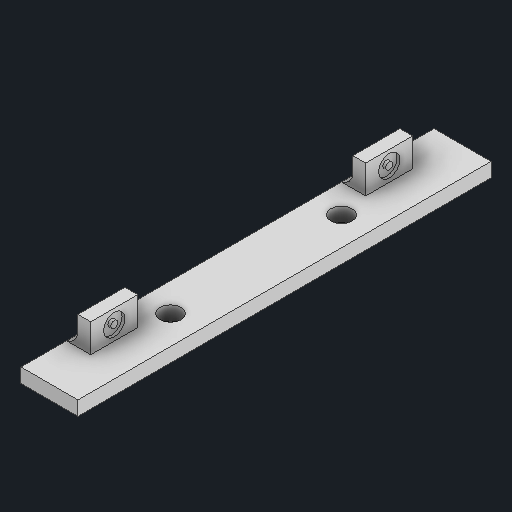
# Autodesk Inventor part: 扭力模块板1
Saved by Autodesk Inventor 2025 (Build 290162000, 162)
## iProperties
Created: 2025-08-27
Part Number: 扭力模块板1
Material: 常规
Document SubType Name: Modeling
Designer: HZD
Density: 1 g/cm^3
Appearance: 默认
Author: HZD
Autodesk Inventor part; units mm, degrees
ref_plane "YZ Plane" through (0, 0, 0) normal (1, 0, 0) x (0, 1, 0)
sketch "草图1" plane through (0, 0, 0) normal (0, 0, 1) x (1, 0, 0)
  line L0 (2, -0.5) -> (-2, -0.5)
  line L1 (-2, -0.5) -> (-2, 0.5)
  line L2 (-2, 0.5) -> (2, 0.5)
  line L3 (2, 0.5) -> (2, -0.5)
  line L4 (2, -0.5) -> (-2, 0.5) construction
  line L5 (-2, -0.5) -> (2, 0.5) construction
  point P0 (0, 0)
  dimension "d0" = 1
  dimension "d1" = 4
  constraints: 12 end point, 2 midpoint, 2 parallel, 1 horizontal, 1 perpendicular
  measures "d0" distance of L2.end L0.start
  measures "d1" distance of L1.end L2.end
extrude "拉伸1" add sketch "草图1" along normal blind 15
sketch "草图2" plane through (-2, 0.5, 0) normal (0, 1, 0) x (1, 0, 0)
  circle A0 centre (2, -13.5) radius 0.75 projected
  circle A1 centre (1.9693, -7.446) radius 0.75 projected
  line L0 (4, 0) -> (0, 0) projected
  line L1 (0, 0) -> (0, -15) projected
  line L2 (4, -15) -> (0, -15) projected
  line L3 (4, 0) -> (4, -15) projected
  circle A2 centre (2, -1.5) radius 0.75 projected
  point P0 (2, 0)
extrude "拉伸2" cut sketch "草图2" against normal blind 15 contours A0 | A2
sketch "草图3" plane through (-2, 0.5, 0) normal (0, 1, 0) x (1, 0, 0)
  line L0 (4, -15) -> (0, -15) projected
  line L1 (0, -15) -> (4, -15)
  line L2 (4, -15) -> (4, -22)
  line L3 (4, -22) -> (0, -22)
  line L4 (0, -22) -> (0, -15)
  line L5 (0, 0) -> (0, -15) projected
  line L6 (0, -7.5) -> (8.0823, -7.5)
  line L7 (4, 0) -> (0, 0)
  line L8 (0, 0) -> (4, 0)
  line L9 (4, 0) -> (4, 7)
  line L10 (4, 7) -> (0, 7)
  line L11 (0, 7) -> (0, 0)
  point P0 (2, 0)
  dimension "d6" = 7
  constraints: 20 end point, 4 symmetric about line, 2 horizontal, 2 parallel, 1 midpoint, 1 perpendicular
  measures "d6" distance of L1.end L2.end
extrude "拉伸3" add sketch "草图3" against normal up to surface (1 mm away)
ref_plane "工作平面2" through (-2.5, 2.1, 0) normal (0, 1, 0) x (0, 0, 1)
sketch "草图4" plane through (-2, 0.5, 22) normal (0, 1, 0) x (1, 0, 0)
  line L0 (4, 22) -> (2, 22)
  line L1 (2, 22) -> (2, 26.3024)
  line L2 (2, 26.3024) -> (4, 26.3024)
  line L3 (4, 26.3024) -> (4, 22)
  line L4 (2, 25.8024) -> (4, 25.8024)
  line L5 (2, 22.5) -> (4, 22.5)
  line L6 (0, 29) -> (0, 0) projected
  line L7 (4, 0) -> (4, 29) projected
  line L8 (2, 22.5) -> (0.8, 22.5)
  line L9 (0.8, 22.5) -> (0.8, 25.8024)
  line L10 (0.8, 25.8024) -> (2, 25.8024)
  line L11 (2, 25.8024) -> (2, 22.5)
  line L12 (1.7, 22.5) -> (1.7, 25.8024)
  dimension "d9" = 0.5
  dimension "d11" = 2
  dimension "d14" = 0
  dimension "d21" = 1.2
  dimension "d22" = 0.3
  constraints: 22 end point, 6 point on line, 5 perpendicular, 4 parallel, 2 horizontal
  measures "d9" distance between parallel lines of L2 L4
  measures "d11" distance between parallel lines of L1 L6
  measures "d14" distance between parallel lines of L3 L7
  measures "d21" distance between parallel lines of L1 L9
  measures "d22" distance between parallel lines of L1 L12
extrude "拉伸4" add sketch "草图4" along normal blind 2 contours L8 L9 L10 L12
ref_plane "工作平面1" through (-2, 0.5, 7.5) normal (0, 0, 1) x (1, 0, 0)
sketch "草图5" plane through (2, -0.5, 22) normal (1, 0, 0) x (0, 0, -1)
  line L0 (22.3024, 2.5989) -> (22.3024, 1.4246) projected
  line L1 (22.3024, 2.0118) -> (26.7599, 2.0118)
  line L2 (24.1512, 2.8941) -> (24.1512, 0.7824)
  circle A0 centre (24.1512, 2.0118) radius 0.75
  line L3 (23.4012, 2.0118) -> (23.4012, 3.0529)
  line L4 (23.4012, 3.0529) -> (24.9012, 3.0529)
  line L5 (24.9012, 3.0529) -> (24.9012, 2.0118)
  point P0 (22, 0.5)
  point P1 (23, 2.6)
  point P2 (25.3024, 2.6)
  dimension "d18" = 1.5
  constraints: 10 end point, 3 point on line, 3 vertical, 2 perpendicular, 2 point on circle, 1 centre point, 1 horizontal, 1 midpoint, 1 tangent
  measures "d18" diameter of A0
extrude "拉伸5" cut sketch "草图5" against normal blind 2.5 contours A0 L2 L1 | L1 L2 A0 | L2 A0 L1 | L1 A0 L2
sketch "草图6" plane through (-0.5, -0.5, 22) normal (1, 0, 0) x (0, 0, -1)
  circle A0 centre (24.1512, 2.0118) radius 0.75 projected
  circle A1 centre (24.1512, 2.0118) radius 0.25
  point P0 (22, 0.5)
  point P1 (24.9012, 2.0118)
  point P2 (23.4012, 2.0118)
  dimension "d23" = 0.5
  constraints: 1 centre point, 1 coincident
  measures "d23" diameter of A1
extrude "拉伸6" add sketch "草图6" along normal up to surface (0.2 mm away) contours A1
mirror "镜像2" about plane through (-2, 0.5, 7.5) normal (0, 0, 1) of "拉伸5", "拉伸4", "拉伸6"
fillet "圆角1" radius 1 2 edges at (-1.2, 0.5, -2.1512) (-1.2, 0.5, 17.1512)
